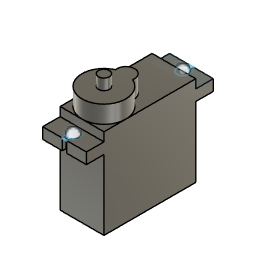
舵機 v1 (Autodesk Fusion 360 design; units mm, degrees)
Autodesk Fusion 360 part; units mm, degrees
sketch "草图1" plane through (0, 0, 0) normal (0, 0, 1) x (1, 0, 0)
  line L0 (0, 0) -> (10, 0)
  line L1 (10, 0) -> (10, 21)
  line L2 (10, 21) -> (0, 21)
  line L3 (0, 21) -> (0, 0)
  dimension "d1" = 10
  dimension "d2" = 21
  constraint horizontal L0
  constraint vertical L1
  constraint horizontal L2
  constraint vertical L3
  constraint coincident L0.start L3.end
  measures "d1" distance of L0.start L0.end
  measures "d2" distance of L0.start L2.end
extrude "拉伸1" add sketch "草图1" along normal blind 20.5
sketch "草图2" plane through (0, 0, 0) normal (0, 1, 0) x (1, 0, 0)
  line L0 (0, -20.5) -> (10, -20.5)
  line L1 (10, -20.5) -> (10, -18.5)
  line L2 (10, -18.5) -> (0, -18.5)
  line L3 (0, -18.5) -> (0, -20.5)
  line L4 (0, -18.5) -> (10, -18.5)
  line L5 (10, -18.5) -> (10, -16)
  line L6 (10, -16) -> (0, -16)
  line L7 (0, -16) -> (0, -18.5)
  dimension "d5" = 2
  constraint horizontal L0
  constraint vertical L1
  constraint horizontal L2
  constraint vertical L3
  constraint horizontal L4
  constraint vertical L5
  constraint horizontal L6
  constraint vertical L7
  measures "d5" distance of L0.start L2.end
extrude "拉伸2" add sketch "草图2" against normal blind 4 contours L2 L4 L5 L6 L7
extrude "拉伸3" add 1 faces at (3.3333, -4, 16.8333) along direction (0, 1, 0) blind 29
sketch "草图3" plane through (0, 0, 20.5) normal (0, 0, 1) x (-1, 0, 0)
  line L0 (0, -21) -> (0, 0)
  line L1 (0, 0) -> (-10, 0)
  line L2 (-10, 0) -> (-10, -21)
  line L3 (-10, -21) -> (0, -21)
  circle A0 centre (-5, -5) radius 5
extrude "拉伸4" add sketch "草图3" along normal blind 4 contours A0
sketch "草图4" plane through (0, 0, 24.5) normal (0, 0, 1) x (-1, 0, 0)
  circle A0 centre (-5, -5) radius 5
  circle A1 centre (-5, -5) radius 1.25
  dimension "d12" = 2.5
  constraint concentric A0 A1
  measures "d12" diameter of A1
extrude "拉伸5" add sketch "草图4" along normal blind 2.5 contours A1
sketch "草图5" plane through (0, 0, 24.5) normal (0, 0, 1) x (-1, 0, 0)
  circle A0 centre (-5, -5) radius 1.25
  circle A1 centre (-5, -5) radius 5
  line L0 (-5, -5) -> (-5, -10)
  circle A2 centre (-5, -10) radius 2
  dimension "d15" = 4
  constraint coincident A0.centre A1.centre
  constraint vertical L0
  constraint coincident L0.end A2.centre
  measures "d15" diameter of A2
extrude "拉伸6" add sketch "草图5" against normal blind 4 contours A1 A2 picked at (-4.5124, -10.5969)
sketch "草图6" plane through (0, 0, 18.5) normal (0, 0, 1) x (-1, 0, 0)
  line L0 (0, -21) -> (-10, -21)
  line L1 (-10, -21) -> (-10, -25)
  line L2 (-10, -25) -> (0, -25)
  line L3 (0, -25) -> (0, -21)
  circle A0 centre (-5, -23) radius 1.25
  circle A1 centre (-5, 2) radius 1.25
  dimension "d18" = 2.5
  dimension "d19" = 2.5
  measures "d18" diameter of A0
  measures "d19" diameter of A1
sketch "草图7" plane through (0, 0, 18.5) normal (0, 0, 1) x (-1, 0, 0)
  line L0 (-4.5, 4) -> (-5.5, 4)
  line L1 (-5.5, 4) -> (-5.5, 3)
  line L2 (-5.5, 3) -> (-4.5, 3)
  line L3 (-4.5, 3) -> (-4.5, 4)
  line L4 (-4.5, -25) -> (-5.5, -25)
  line L5 (-5.5, -25) -> (-5.5, -24)
  line L6 (-5.5, -24) -> (-4.5, -24)
  line L7 (-4.5, -24) -> (-4.5, -25)
  constraint horizontal L0
  constraint vertical L1
  constraint horizontal L2
  constraint vertical L3
  constraint horizontal L4
  constraint vertical L5
  constraint horizontal L6
  constraint vertical L7
extrude "拉伸7" cut sketch "草图6" against normal blind 2 contours A0
extrude "拉伸8" cut sketch "草图7" against normal blind 4 contours L4 L5 L6 L7
extrude "拉伸9" cut sketch "草图6" sketch "草图7" against normal blind 4 contours A1 of sketch 2 contours L0 L1 L2 L3
extrude "拉伸10" cut sketch "草图6" against normal blind 3 contours A0
